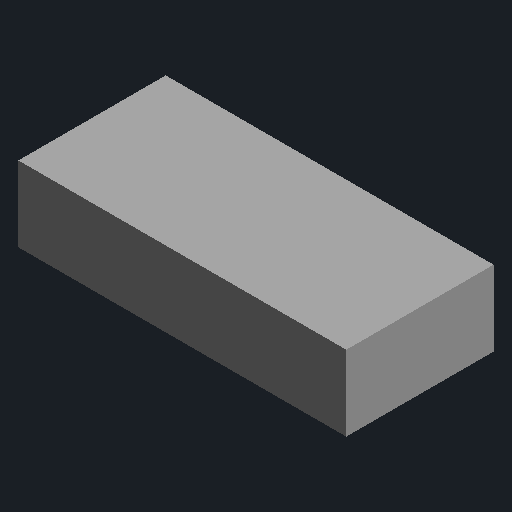
# Autodesk Inventor part: XL4015_52x12x24_acostado
Saved by Autodesk Inventor 2027 (Build 310192060, 192F)
## iProperties
Part Number: XL4015_52x12x24_acostado
Material: Genérico
Document SubType Name: Modelado
Designer: rodri
Appearance: Por defecto
Author: rodri
Autodesk Inventor part; units mm, degrees
sketch "Boceto1" plane through (0, 0, 0) normal (0, 0, 1) x (1, 0, 0)
  line L0 (0, 0) -> (52.3, 0)
  line L1 (52.3, 0) -> (52.3, 12)
  line L2 (52.3, 12) -> (0, 12)
  line L3 (0, 12) -> (0, 0)
  constraints: 8 end point, 2 parallel, 1 horizontal, 1 perpendicular
extrude "Extrusión1" add sketch "Boceto1" along normal blind 23.5
ref_plane "Plano de trabajo1" through (0, 0, 0) normal (0, 1, 0) x (0, 0, 1)
ref_plane "Plano de trabajo2" through (0, 0, 0) normal (1, 0, 0) x (0, 0, -1)
ref_plane "Plano de trabajo3" through (0, 0, 0) normal (0, 1, 0) x (0, 0, 1)
ref_plane "Plano de trabajo4" through (0, 0, 0) normal (1, 0, 0) x (0, 0, -1)
ref_plane "Plano de trabajo5" through (0, 0, 0) normal (0, 1, 0) x (0, 0, 1)
ref_plane "Plano de trabajo6" through (0, 0, 0) normal (1, 0, 0) x (0, 0, -1)
ref_plane "Plano de trabajo7" through (0, 0, 0) normal (0, 1, 0) x (0, 0, 1)
ref_plane "Plano de trabajo8" through (0, 0, 0) normal (1, 0, 0) x (0, 0, -1)
ref_plane "Plano de trabajo9" through (0, 0, 0) normal (0, 1, 0) x (0, 0, 1)
ref_plane "Plano de trabajo10" through (0, 0, 0) normal (1, 0, 0) x (0, 0, -1)
ref_plane "Plano de trabajo11" through (0, 0, 0) normal (0, 1, 0) x (0, 0, 1)
ref_plane "Plano de trabajo12" through (0, 0, 0) normal (1, 0, 0) x (0, 0, -1)
ref_plane "Plano de trabajo13" through (0, 0, 0) normal (0, 1, 0) x (0, 0, 1)
ref_plane "Plano de trabajo14" through (0, 0, 0) normal (1, 0, 0) x (0, 0, -1)
ref_plane "Plano de trabajo15" through (0, 0, 0) normal (0, 1, 0) x (0, 0, 1)
ref_plane "Plano de trabajo16" through (0, 0, 0) normal (1, 0, 0) x (0, 0, -1)
ref_plane "Plano de trabajo17" through (0, 0, 0) normal (0, 1, 0) x (0, 0, 1)
ref_plane "Plano de trabajo18" through (0, 0, 0) normal (1, 0, 0) x (0, 0, -1)
ref_plane "Plano de trabajo19" through (0, 0, 0) normal (0, 1, 0) x (0, 0, 1)
ref_plane "Plano de trabajo20" through (0, 0, 0) normal (1, 0, 0) x (0, 0, -1)
ref_plane "Plano de trabajo21" through (0, 0, 0) normal (0, 1, 0) x (0, 0, 1)
ref_plane "Plano de trabajo22" through (0, 0, 0) normal (1, 0, 0) x (0, 0, -1)
ref_plane "Plano de trabajo23" through (0, 0, 0) normal (0, 1, 0) x (0, 0, 1)
ref_plane "Plano de trabajo24" through (0, 0, 0) normal (1, 0, 0) x (0, 0, -1)
ref_plane "Plano de trabajo25" through (0, 0, 0) normal (0, 1, 0) x (0, 0, 1)
ref_plane "Plano de trabajo26" through (0, 0, 0) normal (1, 0, 0) x (0, 0, -1)
ref_plane "Plano de trabajo27" through (0, 0, 0) normal (0, 1, 0) x (0, 0, 1)
ref_plane "Plano de trabajo28" through (0, 0, 0) normal (1, 0, 0) x (0, 0, -1)
ref_plane "Plano de trabajo29" through (0, 0, 0) normal (0, 1, 0) x (0, 0, 1)
ref_plane "Plano de trabajo30" through (0, 0, 0) normal (1, 0, 0) x (0, 0, -1)
ref_plane "Plano de trabajo31" through (0, 0, 0) normal (0, 1, 0) x (0, 0, 1)
ref_plane "Plano de trabajo32" through (0, 0, 0) normal (1, 0, 0) x (0, 0, -1)
ref_plane "Plano de trabajo33" through (0, 0, 0) normal (0, 1, 0) x (0, 0, 1)
ref_plane "Plano de trabajo34" through (0, 0, 0) normal (1, 0, 0) x (0, 0, -1)
ref_plane "Plano de trabajo35" through (0, 0, 0) normal (0, 1, 0) x (0, 0, 1)
ref_plane "Plano de trabajo36" through (0, 0, 0) normal (1, 0, 0) x (0, 0, -1)
ref_plane "Plano de trabajo37" through (0, 0, 0) normal (0, 1, 0) x (0, 0, 1)
ref_plane "Plano de trabajo38" through (0, 0, 0) normal (1, 0, 0) x (0, 0, -1)
ref_plane "Plano de trabajo39" through (0, 0, 0) normal (0, 1, 0) x (0, 0, 1)
ref_plane "Plano de trabajo40" through (0, 0, 0) normal (1, 0, 0) x (0, 0, -1)
ref_plane "Plano de trabajo41" through (0, 0, 0) normal (0, 1, 0) x (0, 0, 1)
ref_plane "Plano de trabajo42" through (0, 0, 0) normal (1, 0, 0) x (0, 0, -1)
ref_plane "Plano de trabajo43" through (0, 0, 0) normal (0, 1, 0) x (0, 0, 1)
ref_plane "Plano de trabajo44" through (0, 0, 0) normal (1, 0, 0) x (0, 0, -1)
ref_plane "Plano de trabajo45" through (0, 0, 0) normal (0, 1, 0) x (0, 0, 1)
ref_plane "Plano de trabajo46" through (0, 0, 0) normal (1, 0, 0) x (0, 0, -1)
ref_plane "Plano de trabajo47" through (0, 0, 0) normal (0, 1, 0) x (0, 0, 1)
ref_plane "Plano de trabajo48" through (0, 0, 0) normal (1, 0, 0) x (0, 0, -1)
ref_plane "Plano de trabajo49" through (0, 0, 0) normal (0, 1, 0) x (0, 0, 1)
ref_plane "Plano de trabajo50" through (0, 0, 0) normal (1, 0, 0) x (0, 0, -1)
ref_plane "Plano de trabajo51" through (0, 0, 0) normal (0, 1, 0) x (0, 0, 1)
ref_plane "Plano de trabajo52" through (0, 0, 0) normal (1, 0, 0) x (0, 0, -1)
ref_plane "Plano de trabajo53" through (0, 0, 0) normal (0, 1, 0) x (0, 0, 1)
ref_plane "Plano de trabajo54" through (0, 0, 0) normal (1, 0, 0) x (0, 0, -1)
ref_plane "Plano de trabajo55" through (0, 0, 0) normal (0, 1, 0) x (0, 0, 1)
ref_plane "Plano de trabajo56" through (0, 0, 0) normal (1, 0, 0) x (0, 0, -1)
ref_plane "Plano de trabajo57" through (0, 0, 0) normal (0, 1, 0) x (0, 0, 1)
ref_plane "Plano de trabajo58" through (0, 0, 0) normal (1, 0, 0) x (0, 0, -1)
ref_plane "Plano de trabajo59" through (0, 0, 0) normal (0, 1, 0) x (0, 0, 1)
ref_plane "Plano de trabajo60" through (0, 0, 0) normal (1, 0, 0) x (0, 0, -1)
ref_plane "Plano de trabajo61" through (0, 0, 0) normal (0, 1, 0) x (0, 0, 1)
ref_plane "Plano de trabajo62" through (0, 0, 0) normal (1, 0, 0) x (0, 0, -1)
ref_plane "Plano de trabajo63" through (0, 0, 0) normal (0, 1, 0) x (0, 0, 1)
ref_plane "Plano de trabajo64" through (0, 0, 0) normal (1, 0, 0) x (0, 0, -1)
ref_plane "Plano de trabajo65" through (0, 0, 0) normal (0, 1, 0) x (0, 0, 1)
ref_plane "Plano de trabajo66" through (0, 0, 0) normal (1, 0, 0) x (0, 0, -1)
ref_plane "Plano de trabajo67" through (0, 0, 0) normal (0, 1, 0) x (0, 0, 1)
ref_plane "Plano de trabajo68" through (0, 0, 0) normal (1, 0, 0) x (0, 0, -1)
ref_plane "Plano de trabajo69" through (0, 0, 0) normal (0, 1, 0) x (0, 0, 1)
ref_plane "Plano de trabajo70" through (0, 0, 0) normal (1, 0, 0) x (0, 0, -1)
ref_plane "Plano de trabajo71" through (0, 0, 0) normal (0, 1, 0) x (0, 0, 1)
ref_plane "Plano de trabajo72" through (0, 0, 0) normal (1, 0, 0) x (0, 0, -1)
ref_plane "Plano de trabajo73" through (0, 0, 0) normal (0, 1, 0) x (0, 0, 1)
ref_plane "Plano de trabajo74" through (0, 0, 0) normal (1, 0, 0) x (0, 0, -1)
ref_plane "Plano de trabajo75" through (0, 0, 0) normal (0, 1, 0) x (0, 0, 1)
ref_plane "Plano de trabajo76" through (0, 0, 0) normal (1, 0, 0) x (0, 0, -1)
ref_plane "Plano de trabajo77" through (0, 0, 0) normal (0, 1, 0) x (0, 0, 1)
ref_plane "Plano de trabajo78" through (0, 0, 0) normal (1, 0, 0) x (0, 0, -1)
ref_plane "Plano de trabajo79" through (0, 0, 0) normal (0, 1, 0) x (0, 0, 1)
ref_plane "Plano de trabajo80" through (0, 0, 0) normal (1, 0, 0) x (0, 0, -1)
ref_plane "Plano de trabajo81" through (0, 0, 0) normal (0, 1, 0) x (0, 0, 1)
ref_plane "Plano de trabajo82" through (0, 0, 0) normal (1, 0, 0) x (0, 0, -1)
ref_plane "Plano de trabajo83" through (0, 0, 0) normal (0, 1, 0) x (0, 0, 1)
ref_plane "Plano de trabajo84" through (0, 0, 0) normal (1, 0, 0) x (0, 0, -1)
ref_plane "Plano de trabajo85" through (0, 0, 0) normal (0, 1, 0) x (0, 0, 1)
ref_plane "Plano de trabajo86" through (0, 0, 0) normal (1, 0, 0) x (0, 0, -1)
ref_plane "Plano de trabajo87" through (0, 0, 0) normal (0, 1, 0) x (0, 0, 1)
ref_plane "Plano de trabajo88" through (0, 0, 0) normal (1, 0, 0) x (0, 0, -1)
ref_plane "Plano de trabajo89" through (0, 0, 0) normal (0, 1, 0) x (0, 0, 1)
ref_plane "Plano de trabajo90" through (0, 0, 0) normal (1, 0, 0) x (0, 0, -1)
ref_plane "Plano de trabajo91" through (0, 0, 0) normal (0, 1, 0) x (0, 0, 1)
ref_plane "Plano de trabajo92" through (0, 0, 0) normal (1, 0, 0) x (0, 0, -1)
ref_plane "Plano de trabajo93" through (0, 0, 0) normal (0, 1, 0) x (0, 0, 1)
ref_plane "Plano de trabajo94" through (0, 0, 0) normal (1, 0, 0) x (0, 0, -1)
ref_plane "Plano de trabajo95" through (0, 0, 0) normal (0, 1, 0) x (0, 0, 1)
ref_plane "Plano de trabajo96" through (0, 0, 0) normal (1, 0, 0) x (0, 0, -1)
ref_plane "Plano de trabajo97" through (0, 0, 0) normal (0, 1, 0) x (0, 0, 1)
ref_plane "Plano de trabajo98" through (0, 0, 0) normal (1, 0, 0) x (0, 0, -1)
ref_plane "Plano de trabajo99" through (0, 0, 0) normal (0, 1, 0) x (0, 0, 1)
ref_plane "Plano de trabajo100" through (0, 0, 0) normal (1, 0, 0) x (0, 0, -1)
ref_plane "Plano de trabajo101" through (0, 0, 0) normal (0, 1, 0) x (0, 0, 1)
ref_plane "Plano de trabajo102" through (0, 0, 0) normal (1, 0, 0) x (0, 0, -1)
ref_plane "Plano de trabajo103" through (0, 0, 0) normal (0, 1, 0) x (0, 0, 1)
ref_plane "Plano de trabajo104" through (0, 0, 0) normal (1, 0, 0) x (0, 0, -1)
ref_plane "Plano de trabajo105" through (0, 0, 0) normal (0, 1, 0) x (0, 0, 1)
ref_plane "Plano de trabajo106" through (0, 0, 0) normal (1, 0, 0) x (0, 0, -1)
ref_plane "Plano de trabajo107" through (0, 0, 0) normal (0, 1, 0) x (0, 0, 1)
ref_plane "Plano de trabajo108" through (0, 0, 0) normal (1, 0, 0) x (0, 0, -1)
ref_plane "Plano de trabajo109" through (0, 0, 0) normal (0, 1, 0) x (0, 0, 1)
ref_plane "Plano de trabajo110" through (0, 0, 0) normal (1, 0, 0) x (0, 0, -1)
